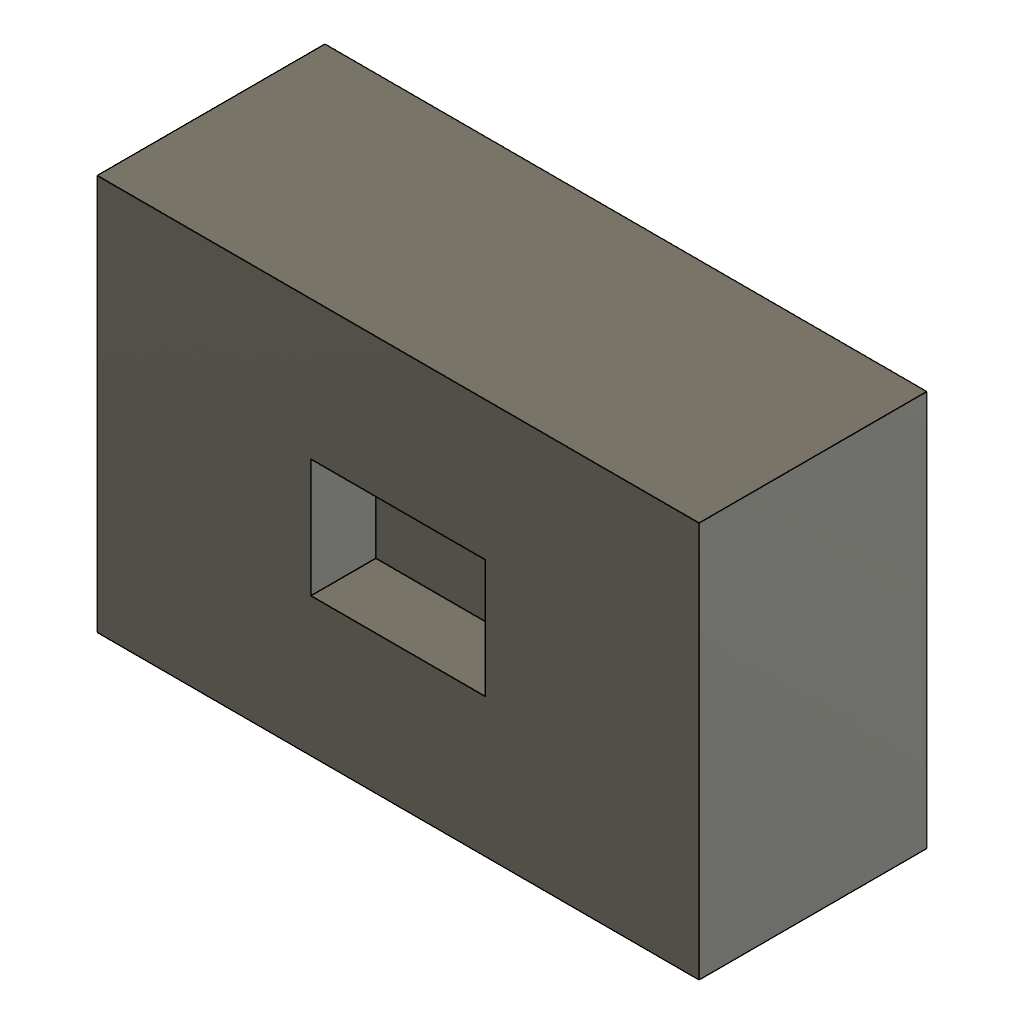
CutHoldout (Autodesk Fusion 360 design; units mm, degrees)
part number: 2026-11-23-18-10-16-588
Autodesk Fusion 360 part; units mm, degrees
sketch "RectangleSketch" plane through (0, 0, 0) normal (0, 0, 1) x (1, 0, 0)
  line L0 (0, 0) -> (47.3, 0)
  line L1 (47.3, 0) -> (47.3, 31.1)
  line L2 (47.3, 31.1) -> (0, 31.1)
  line L3 (0, 31.1) -> (0, 0)
  dimension "width_mm" = 47.3
  dimension "height_mm" = 31.1
  constraint horizontal L0
  constraint vertical L1
  constraint horizontal L2
  constraint vertical L3
  constraint coincident L0.start L3.end
  measures "width_mm" horizontal distance of L0.start L0.end
  measures "height_mm" vertical distance of L0.start L2.end
extrude "BlindBoss" add sketch "RectangleSketch" along normal blind 17.9
sketch "CutSketch" plane through (0, 0, 17.9) normal (0, 0, 1) x (1, 0, 0)
  line L0 (0, 31.1) -> (0, 0)
  line L1 (0, 0) -> (47.3, 0)
  line L2 (47.3, 0) -> (47.3, 31.1)
  line L3 (47.3, 31.1) -> (0, 31.1)
  line L4 (16.8, 10.9) -> (30.5, 10.9)
  line L5 (30.5, 10.9) -> (30.5, 20.2)
  line L6 (30.5, 20.2) -> (16.8, 20.2)
  line L7 (16.8, 20.2) -> (16.8, 10.9)
  line L8 (16.8, 10.9) -> (30.5, 20.2) construction
  point P0 (23.65, 15.55)
  dimension "cut_width_mm" = 13.7
  dimension "cut_height_mm" = 9.3
  dimension "cut_center_u_mm" = 23.65
  dimension "cut_center_v_mm" = 15.55
  constraint horizontal L4
  constraint vertical L5
  constraint horizontal L6
  constraint vertical L7
  constraint midpoint L8 P0
  measures "cut_width_mm" horizontal distance of L4.start L4.end
  measures "cut_height_mm" vertical distance of L4.start L6.end
  measures "cut_center_u_mm" horizontal distance of P0 L0.end
  measures "cut_center_v_mm" vertical distance of P0 L0.end
extrude "BlindCut" cut sketch "CutSketch" against normal blind 5.1 contours L4 L5 L6 L7
equation "depth_mm = 17.899999999999999 mm"
equation "cut_center_u_mm = width_mm / 2"
equation "cut_center_v_mm = height_mm / 2"
equation "cut_depth_mm = -5.0999999999999996 mm"
